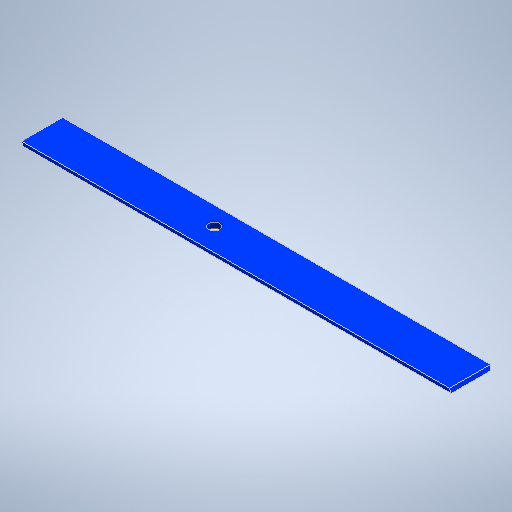
# Autodesk Inventor part: Higher_Section_Plate2
Saved by Autodesk Inventor 2026.2 (Build 302298000, 298)
## iProperties
Created: 2026-07-14
Part Number: Higher_Section_Plate2
Material: M-Foam PVC foam
Document SubType Name: Modeling
Designer: Taiye Raji
Density: 0.13 g/cm^3
Appearance: Generic
Mass: 596.309 g
Surface Area: 5314.78 cm^2
Volume: 4586.99 cm^3
Author: Taiye Raji
Autodesk Inventor part; units mm, degrees
ref_plane "YZ Plane" through (0, 0, 0) normal (1, 0, 0) x (0, 1, 0)
ref_plane "XZ Plane" through (0, 0, 0) normal (0, 1, 0) x (-1, 0, 0)
ref_plane "XY Plane" through (0, 0, 0) normal (0, 0, 1) x (1, 0, 0)
sketch "Sketch1" plane through (0, 0, 0) normal (0, 1, 0) x (-1, 0, 0)
  line L0 (-783, 75.7572) -> (783, 75.7572)
  line L1 (783, 75.7572) -> (783, -75.7572)
  line L2 (783, -75.7572) -> (-783, -75.7572)
  line L3 (-783, -75.7572) -> (-783, 75.7572)
  line L4 (-783, 75.7572) -> (783, -75.7572) construction
  line L5 (783, 75.7572) -> (-783, -75.7572) construction
  point P0 (0, 0)
  dimension "d0" = 1566
  dimension "d1" = 151.5145
  constraints: 12 end point, 2 midpoint, 2 parallel, 1 horizontal, 1 perpendicular
  measures "d0" distance of L1.end L2.end
  measures "d1" distance of L2.end L0.start
extrude "Extrusion1" add sketch "Sketch1" along normal blind 20
sketch "Sketch2" plane through (783, 0, 75.7572) normal (1, 0, 0) x (0, 0, -1)
  line L0 (0, 0) -> (6.4984, 20)
  line L1 (151.5145, 20) -> (0, 20) projected
  line L2 (6.4984, 20) -> (151.5145, 20)
  line L3 (151.5145, 0) -> (151.5145, 20) projected
  line L4 (151.5145, 20) -> (151.5145, 0)
  line L5 (151.5145, 0) -> (0, 0)
  line L6 (0, 0) -> (0, 20)
  line L7 (6.4984, 20) -> (6.4984, 0)
  line L8 (6.4984, 0) -> (0, 20)
  point P0 (75.7572, 0)
  point P1 (6.4984, 20)
  point P2 (3.2492, 10)
  point P3 (0, 21)
  point P4 (6.4984, 20)
  point P5 (0, 21)
  dimension "d21" = 72
  constraints: 14 end point, 3 perpendicular, 1 collinear, 1 point on line, 1 vertical
  measures "d21" angle of L5 L0
extrude "Extrusion2" cut sketch "Sketch2" against normal blind 1566 contours L6 L8 L0 | L0 L8 L5
sketch "Sketch3" plane through (0, 20, 0) normal (0, 1, 0) x (1, 0, 0)
  line L0 (783, -75.7572) -> (783, 75.7572) projected
  circle A0 centre (-160, 6.3378) radius 20
  line L1 (-783, -75.7572) -> (783, -75.7572) projected
  point P0 (0, 0)
  point P1 (783, 0)
  point P2 (783, 0)
  dimension "d16" = 160
  dimension "d17" = 82.095
  dimension "d18" = 40
  constraints: 2 midpoint, 1 centre point
  measures "d16" horizontal distance of A0.centre point (0, 0)
  measures "d17" distance from line of A0.centre L1
  measures "d18" diameter of A0
extrude "Extrusion3" cut sketch "Sketch3" against normal blind 20
move faces "Move1" translate (0, 0, 0.832) faces at (261, 6.6667, -75.7572)
move faces "Move2" translate (0, 0, 0.1875) faces at (261, 6.6667, -74.9252)
body "Solid1"
